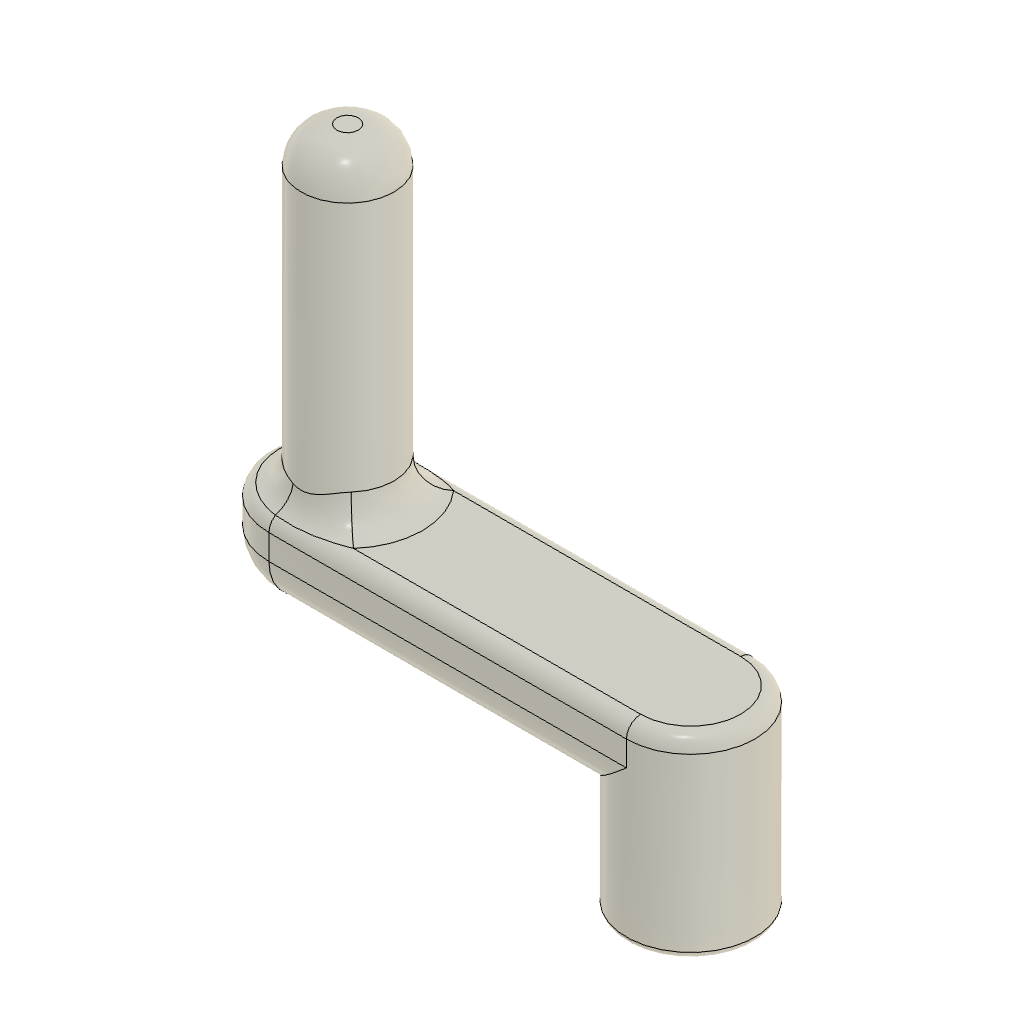
handle (Autodesk Fusion 360 design; units mm, degrees)
part number: 2026-09-20-00-21-26-422
Autodesk Fusion 360 part; units mm, degrees
sketch "Sketch1" plane through (0, 0, 0) normal (0, 0, 1) x (1, 0, 0)
  line L0 (3.85, 3.85) -> (-3.85, 3.85)
  line L1 (-3.85, 3.85) -> (-3.85, -3.85)
  line L2 (-3.85, -3.85) -> (3.85, -3.85)
  line L3 (3.85, -3.85) -> (3.85, 3.85)
  line L4 (3.85, 3.85) -> (-3.85, -3.85) construction
  line L5 (-3.85, 3.85) -> (3.85, -3.85) construction
  circle A0 centre (0, 0) radius 9
  dimension "d1" = 7.7
  dimension "d2" = 7.7
  dimension "d3" = 18
  constraint horizontal L0
  constraint perpendicular L0 L1
  constraint parallel L0 L2
  constraint parallel L1 L3
  constraint coincident L4 A0.centre
  constraint coincident L5 A0.centre
  constraint coincident A0.centre origin
  measures "d1" distance of L0.end L1.end
  measures "d2" distance of L1.end L2.end
  measures "d3" diameter of A0
extrude "Extrude1" add sketch "Sketch1" along normal blind 15
sketch "Sketch2" plane through (0, 0, 15) normal (0, 0, 1) x (-1, 0, 0)
  line L0 (-3.85, -3.85) -> (-3.85, 3.85)
  line L1 (-3.85, 3.85) -> (3.85, 3.85)
  line L2 (3.85, 3.85) -> (3.85, -3.85)
  line L3 (3.85, -3.85) -> (-3.85, -3.85)
  circle A0 centre (0, 0) radius 9
  circle A1 centre (50, -0.001) radius 9
  line L4 (49.9998, -9.001) -> (-0.0002, -9)
  line L5 (50.0002, 8.999) -> (0.0002, 9)
  point P0 (50, -0.001)
  dimension "d6" = 50
  dimension "d7" = 18
  dimension "d8" = 50
  constraint coincident P0 A1.centre
  constraint coincident A1 L4.start
  constraint coincident A0 L4.end
  constraint tangent A0 L4
  constraint coincident A1 L5.start
  constraint coincident A0 L5.end
  constraint tangent A0 L5
  constraint tangent A1 L4
  constraint tangent A1 L5
  measures "d6" distance of A0.centre A1.centre
  measures "d7" diameter of A1
  measures "d8" horizontal distance of L4.start L4.end
extrude "Extrude2" add sketch "Sketch2" along normal blind 12 contours L0 L1 L2 L3 | A0 | A0 A1 L4 L5 | A1
sketch "Sketch5" plane through (0, 0, 27) normal (0, 0, 1) x (-1, 0, 0)
  arc A0 (49.9998, -9.001) -> (50.0002, 8.999) centre (50, -0.001) ccw
  line L0 (50.0002, 8.999) -> (0.0002, 9)
  arc A1 (0.0002, 9) -> (-0.0002, -9) centre (0, 0) ccw
  line L1 (-0.0002, -9) -> (49.9998, -9.001)
  circle A2 centre (48, -0.001) radius 6.5
  dimension "d14" = 13
  dimension "d15" = 48
  measures "d14" diameter of A2
  measures "d15" horizontal distance of A1.centre A2.centre
extrude "Extrude3" add sketch "Sketch5" along normal blind 44 contours A2
fillet "Fillet2" radius 5 1 edges at (-41.9399, 2.3515, 71)
fillet "Fillet4" radius 0.5 4 edges at (3.85, 0, 0) (0, -3.85, 0) (-3.85, 0, 0) (0, 3.85, 0)
fillet "Fillet5" radius 6.5 3 edges at (-24.9998, 9.0005, 15) (-59, 0.0012, 15) (-25.0002, -8.9995, 15)
fillet "Fillet6" radius 1 1 edges at (-8.3909, -3.2545, 0)
fillet "Fillet7" radius 2 4 edges at (9, -0.0002, 27) (-24.9998, 9.0005, 27) (-59, 0.0012, 27) (-25.0002, -8.9995, 27)
fillet "Fillet8" radius 4 1 edges at (-41.9399, -2.3495, 27)
